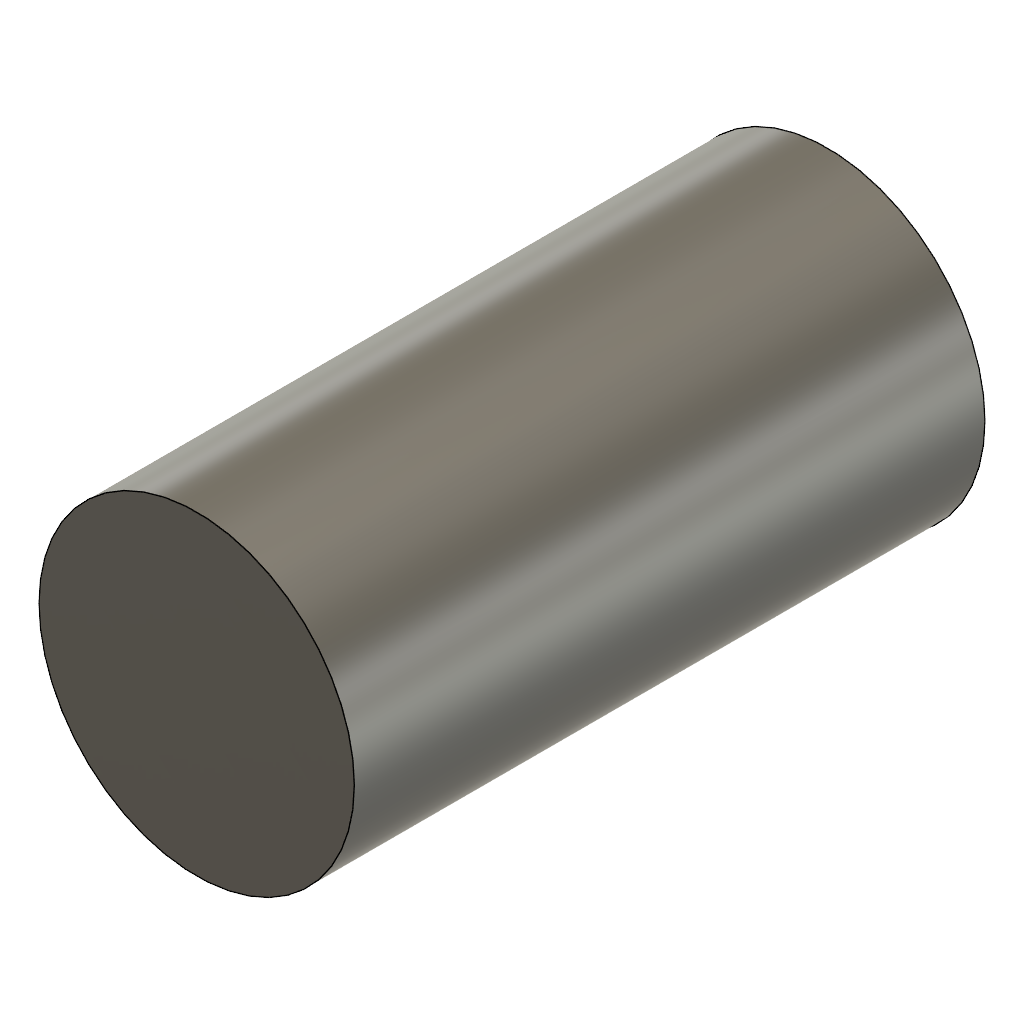
DiscHalf (Autodesk Fusion 360 design; units mm, degrees)
part number: 2026-11-22-11-29-41-524
Autodesk Fusion 360 part; units mm, degrees
sketch "Disc sketch" plane through (0, 0, 0) normal (0, 0, 1) x (1, 0, 0)
  circle A0 centre (20, 15) radius 10
extrude "Disc extrude" add sketch "Disc sketch" along normal mid plane 40
